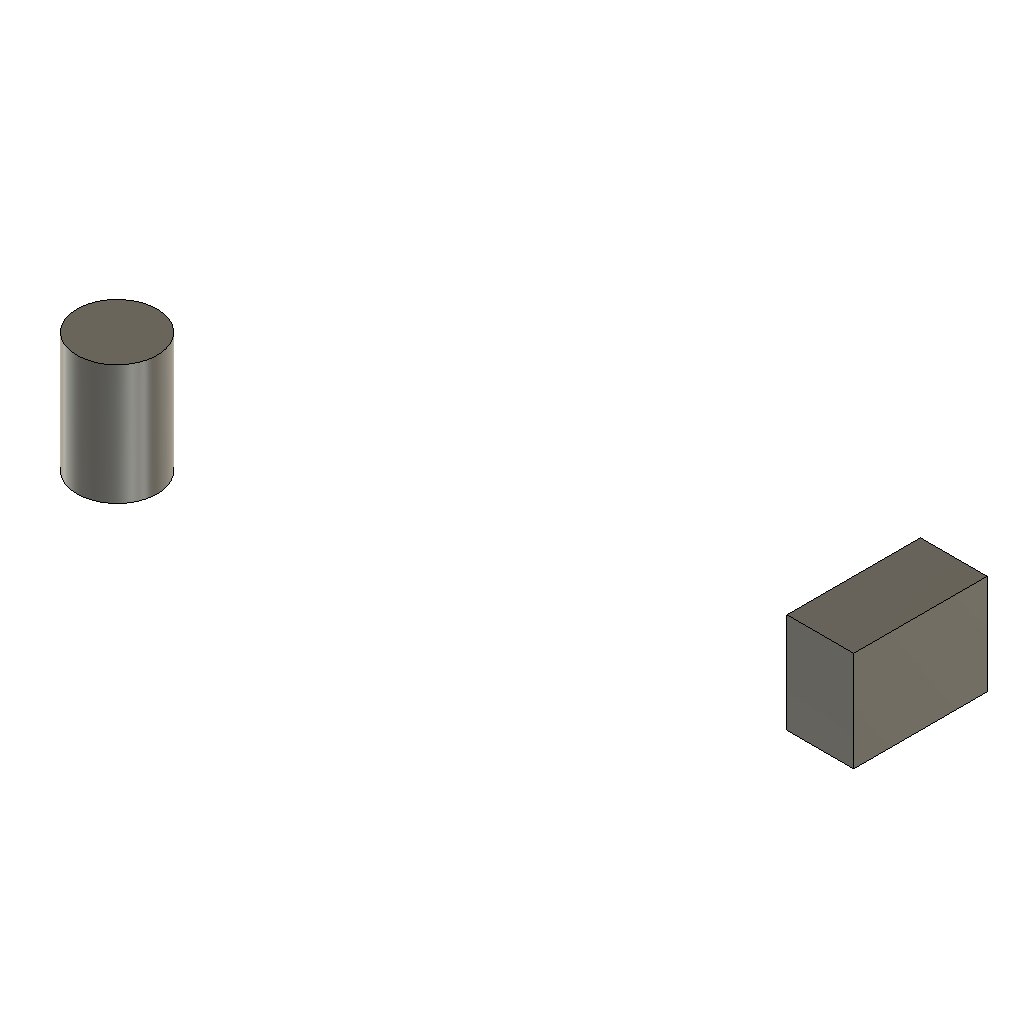
f2sc-ttest-primitives (Autodesk Fusion 360 design; units mm, degrees)
part number: 2026-11-27-14-34-52-355
Autodesk Fusion 360 part; units mm, degrees
box "BoxPrimitive1" add length 20 width 10 height 15 placed x (0, 1, 0) y (-1, 0, 0) z (0, 0, 1) at (53.8975, 6.5197, 0) makes body 1
cylinder "CylinderPrimitive1" add diameter 12 height 18 placed x (1, 0, 0) y (0, 1, 0) z (0, 0, 1) at (-40, -10, 0) separate body makes body 2
